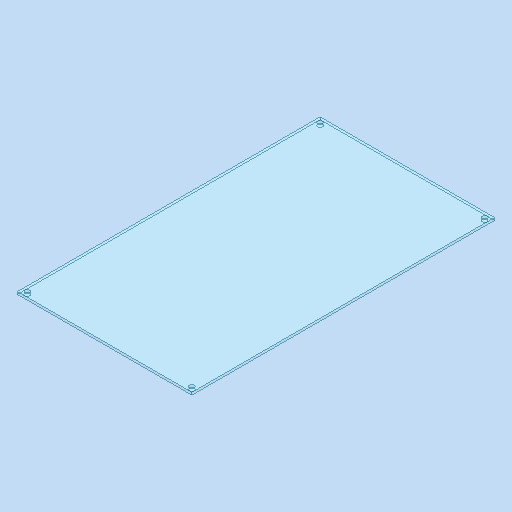
# Autodesk Inventor part: MM0861AN200_G22_149
Saved by Autodesk Inventor 2023.3 (Build 273359000, 359)
## iProperties
Part Number: MM0861AN200_G22_149
Material: Kst - PC (Eslon, klar)
Description: =<RBPARTNOTITLE2>
Document SubType Name: Modeling
Designer: Benutzer
Mass: 666.009 g
Surface Area: 2840.98 cm^2
Volume: 555.008 cm^3
Density: 1.2 g/cm^3
Appearance: Klar AnP
Vendor: Koenig
RBDOCUMENTTYPE: DRF
RBDOCUMENTVERSION: 00
RBDRAWINGMAINSCALE: 1:1
RBDRAWINGMISSINGSPEC: --
RBDRAWINGVOLUME: --
RBGBEDGESIN1: +0,5
RBGBEDGESIN2: +0,2
RBGBEDGESOUT1: -0,3
RBGBEDGESOUT2: -0,1
RBMATERIAL: =<Material>
RBMATMEETS: --
RBMATNO: =<Part Number>
RBPARTMADEOF: 4 x 491 x 283 (FM)
RBPARTNO: SIEHE MNR
RBPARTNOTITLE1: manufactured part
RBPARTNOTITLE2: Anfertigungsteil
RBPARTSAFETYINDICATOR: --
RBSURFACE: --
RBSURFACE2: --
RBZEDGESNORM: ISO13715:2002-06
RBZGENDIMCLASS: m
RBZGENDIMNORM: ISO 2768-1:1989-11
RBZGENGEOCLASS: H
RBZGENGEONORM: ISO 2768-2:1989-11
RBZSURFACENORM: ISO13D2:2002-02
RBZTOLERANCENORM: ISO 14405-1:2010-12
AnP_Material: =<Material>
AnP_TemplVers: 20190222
AnP_Kategorie: 1
MaxAbmaße: 4 x 491 x 283 (FM)
Author: Benutzer
Keywords: =<RBPARTMADEOF>
Comments: =<RBSURFACE2>
Revision Number: 01
Autodesk Inventor part; units mm, degrees
ref_plane "YZ Plane" through (0, 0, 0) normal (1, 0, 0) x (0, 1, 0)
ref_plane "XZ Plane" through (0, 0, 0) normal (0, 1, 0) x (-1, 0, 0)
ref_plane "XY Plane" through (0, 0, 0) normal (0, 0, 1) x (1, 0, 0)
sketch "Skizze1" plane through (0, 0, 0) normal (0, 0, 1) x (1, 0, 0)
  line L0 (0, 0) -> (283, 0)
  line L1 (283, 0) -> (283, 491)
  line L2 (283, 491) -> (0, 491)
  line L3 (0, 491) -> (0, 0)
  dimension "d0" = 283
  dimension "d1" = 491
  constraints: 8 end point, 2 parallel, 1 horizontal, 1 perpendicular
  measures "d0" distance of L2.end L1.end
  measures "d1" distance of L1.end L0.end
extrude "Extrusion1" add sketch "Skizze1" along normal blind 4
sketch "Skizze2" plane through (0, 0, 4) normal (0, 0, 1) x (1, 0, 0)
  line L0 (0, 491) -> (0, 0) projected
  line L1 (283, 491) -> (0, 491) projected
  line L2 (283, 0) -> (283, 491) projected
  line L3 (0, 0) -> (283, 0) projected
  point P0 (8, 483)
  point P1 (275, 483)
  point P2 (275, 8)
  point P3 (8, 8)
  dimension "d4" = 8
  dimension "d5" = 8
  dimension "d6" = 8
  dimension "d7" = 8
  constraints: 2 horizontal alignment, 2 vertical alignment
  measures "d4" distance from line of L0 point (8, 483)
  measures "d5" distance from line of L1 point (8, 483)
  measures "d6" distance from line of L2 point (275, 483)
  measures "d7" distance from line of L3 point (275, 8)
hole "Bohrung1" at (8, 483, 4) at (275, 483, 4) at (275, 8, 4) at (8, 8, 4) direction (0, 0, -1) diameter 8 depth 8 tip angle 118
